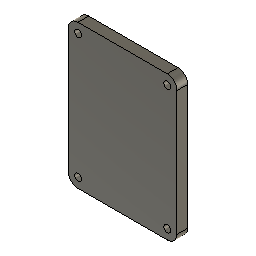
Total_Drone_Assembly_FinalVersion (Autodesk Fusion 360 archive; units mm, degrees)
design "Claw Mount"
Autodesk Fusion 360 part; units mm, degrees
sketch "Sketch1" plane through (0, 0, 0) normal (0, 1, 0) x (1, 0, 0)
  line L0 (20.785, 29) -> (-20.785, 29) construction
  line L1 (-20.785, 29) -> (-20.785, -29) construction
  line L2 (-20.785, -29) -> (20.785, -29) construction
  line L3 (20.785, -29) -> (20.785, 29) construction
  line L4 (20.785, 29) -> (-20.785, -29) construction
  line L5 (-20.785, 29) -> (20.785, -29) construction
  circle A0 centre (-20.785, -29) radius 1.6
  circle A1 centre (20.785, -29) radius 1.6
  circle A2 centre (-20.785, 29) radius 1.6
  circle A3 centre (20.785, 29) radius 1.6
  line L6 (-25.3048, 28.5198) -> (-25.3048, -28.5198)
  line L7 (-20.3048, -33.5198) -> (20.3048, -33.5198)
  line L8 (25.3048, -28.5198) -> (25.3048, 28.5198)
  line L9 (20.3048, 33.5198) -> (-20.3048, 33.5198)
  line L10 (-25.3048, -28.5198) -> (-25.3048, -33.5198)
  line L11 (-25.3048, -33.5198) -> (-20.3048, -33.5198)
  line L12 (0, 0) -> (4, 0) construction
  line L13 (0, 0) -> (0, -6) construction
  line L14 (25.3048, -28.5198) -> (25.3048, -33.5198)
  line L15 (25.3048, -33.5198) -> (20.3048, -33.5198)
  line L16 (-25.3048, 28.5198) -> (-25.3048, 33.5198)
  line L17 (-25.3048, 33.5198) -> (-20.3048, 33.5198)
  line L18 (25.3048, 33.5198) -> (20.3048, 33.5198)
  line L19 (25.3048, 28.5198) -> (25.3048, 33.5198)
  dimension "d2" = 58
  dimension "d3" = 3.2
  dimension "d8" = 41.57
  constraint horizontal L0
  constraint perpendicular L0 L1
  constraint parallel L0 L2
  constraint parallel L1 L3
  constraint coincident L4 L12.start
  constraint coincident L5 L12.start
  constraint coincident L12.start L13.start
  constraint coincident L1.end L2.start
  constraint coincident L2.end L3.start
  constraint coincident L0.end L1.start
  constraint coincident L0.start L3.end
  constraint equal A0 A1
  constraint equal A1 A2
  constraint equal A1 A3
  constraint perpendicular L7 L10
  constraint perpendicular L10 L11
  constraint horizontal L12
  constraint perpendicular L12 L13
  constraint symmetric L6.end L13 L8.start
  constraint symmetric L7.start L13 L7.end
  constraint symmetric L10.end L13 L14.end
  constraint symmetric L6.end L12 L6.start
  constraint symmetric L7.start L12 L9.end
  constraint symmetric L10.end L12 L16.end
  constraint symmetric L12 L8.start L8.end
  constraint symmetric L12 L14.end L18.start
  constraint symmetric L12 L7.end L9.start
  measures "d2" distance of L0 L2
  measures "d3" diameter of A0
  measures "d8" distance of L0.end L0.start
extrude "Extrude1" add sketch "Sketch1" against normal blind 5
fillet "Fillet1" radius 4.5 1 edges at (25.3048, -2.5, 33.5198)
fillet "Fillet1" radius 4.5 1 edges at (-25.3048, -2.5, 33.5198)
fillet "Fillet1" radius 4.5 1 edges at (-25.3048, -2.5, -33.5198)
fillet "Fillet1" radius 4.5 1 edges at (25.3048, -2.5, -33.5198)

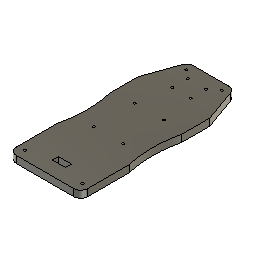
design "Upper Frame Plate"
Autodesk Fusion 360 part; units mm, degrees
sketch "Sketch2" plane through (0, 0, 0) normal (0, 0, 1) x (1, 0, 0)
  arc A0 (50.78, 25.1156) -> (50.78, -49.0914) centre (208.9874, -11.9879) ccw
  arc A1 (-50.78, -49.0914) -> (-50.78, 25.1156) centre (-208.9874, -11.9879) ccw
  circle A2 centre (-20.7745, -27.75) radius 1.6
  circle A3 centre (20.7855, -27.75) radius 1.6
  line L0 (50.78, 117.78) -> (-50.78, -117.78) construction
  line L1 (-50.78, 117.78) -> (50.78, -117.78) construction
  arc A4 (-50.78, -107.78) -> (-40.78, -117.78) centre (-40.78, -107.78) ccw
  line L2 (0, 0) -> (-7.4341, 0) construction
  line L3 (50.78, 65.1233) -> (50.78, 25.1156)
  circle A5 centre (40.78, -105.28) radius 1.6
  line L4 (-50.78, 65.1233) -> (-34.4616, 111.1233)
  line L5 (-50.78, 65.1233) -> (-50.78, 25.1156)
  circle A6 centre (-40.78, -105.28) radius 1.6
  circle A7 centre (25.0371, 107.78) radius 1.6
  line L6 (50.78, 65.1233) -> (34.4616, 111.1233)
  line L7 (-50.78, -65.1233) -> (50.78, -65.1233) construction
  line L8 (-50.78, -49.0914) -> (-50.78, -107.78)
  line L9 (0, 0) -> (0, 7) construction
  line L10 (-40.78, -117.78) -> (40.78, -117.78)
  line L11 (-51.3517, 117.78) -> (-25.0371, 117.78)
  line L12 (50.78, -107.78) -> (50.78, -49.0914)
  line L13 (-50.78, 65.1233) -> (50.78, 65.1233) construction
  circle A8 centre (-25.0371, 107.78) radius 1.6
  arc A9 (40.78, -117.78) -> (50.78, -107.78) centre (40.78, -107.78) ccw
  arc A10 (34.4616, 111.1233) -> (25.0371, 117.78) centre (25.0371, 107.78) ccw
  circle A11 centre (20.7855, 30.25) radius 1.6
  line L14 (-40.78, -107.78) -> (-45.5769, -105.7118)
  circle A12 centre (-20.7745, 30.25) radius 1.6
  arc A13 (-25.0371, 117.78) -> (-34.4616, 111.1233) centre (-25.0371, 107.78) ccw
  line L15 (-51.3517, 117.78) -> (25.0371, 117.78)
  line L16 (0, 0) -> (0, -8) construction
  line L17 (-9.25, -89.28) -> (9.25, -89.28)
  line L18 (9.25, -89.28) -> (9.25, -97.78)
  line L19 (9.25, -97.78) -> (-9.25, -97.78)
  line L20 (-9.25, -97.78) -> (-9.25, -89.28)
  line L21 (-9.25, -89.28) -> (9.25, -97.78) construction
  line L22 (9.25, -89.28) -> (-9.25, -97.78) construction
  circle A14 centre (12.78, 76.16) radius 1.6
  circle A15 centre (-13.22, 76.16) radius 1.6
  circle A16 centre (12.78, 97.78) radius 1.6
  circle A17 centre (-13.22, 97.78) radius 1.6
  point P0 (-50.78, -49.0914)
  point P1 (25.2318, 134.4238)
  point P2 (-20.0717, 32.7459)
  point P3 (0, -15.28)
  point P4 (0, 15)
  point P5 (0, 55)
  point P6 (0, -55)
  point P7 (-20.0606, -58.0786)
  point P8 (20.4874, -58.0786)
  point P9 (0, -93.53)
  dimension "d145" = 41.56
  dimension "d146" = 101.56
  dimension "d147" = 235.56
  dimension "d148" = 60.5
  dimension "d149" = 30.0055
  dimension "d150" = 145.53
  dimension "d151" = 10
  dimension "d152" = 10
  dimension "d156" = 15.28
  dimension "d159" = 160.468
  dimension "d160" = 10
  dimension "d161" = 46
  dimension "d162" = 110
  dimension "d163" = 162.5
  dimension "d164" = 208.9874
  dimension "d165" = 105.7921
  dimension "d166" = 3.2
  dimension "d167" = 3.2
  dimension "d168" = 3.2
  dimension "d169" = 3.2
  dimension "d170" = 3.2
  dimension "d171" = 3.2
  dimension "d172" = 3.2
  dimension "d173" = 3.2
  dimension "d176" = 101.56
  dimension "d189" = 18.5
  dimension "d190" = 8.5
  dimension "d191" = 20
  dimension "d195" = 90.03
  dimension "d196" = 3.2
  dimension "d197" = 3.2
  dimension "d198" = 26
  dimension "d200" = 38
  dimension "d201" = 3.2
  dimension "d203" = 3.2
  dimension "d204" = 21.62
  dimension "d207" = 20
  dimension "d208" = 26
  dimension "d209" = 21.62
  constraint coincident L2.start L9.start
  constraint horizontal L11
  constraint perpendicular L5 L11
  constraint parallel L10 L11
  constraint parallel L5 L12
  constraint coincident L2.start L0
  constraint coincident L2.start L1
  constraint coincident L0.end L5
  constraint coincident L0.end L10
  constraint tangent A4 L5
  constraint tangent A4 L10
  constraint coincident L1.end L12
  constraint coincident L1.end L10
  constraint tangent L12 A9
  constraint tangent L10 A9
  constraint coincident L1.start L11
  constraint coincident L1.start L5
  constraint coincident L0.start L11
  constraint coincident L0.start L12
  constraint coincident A4.centre L14.start
  constraint coincident L14.end L0
  constraint perpendicular L0 L14
  constraint horizontal L2
  constraint perpendicular L2 L9
  constraint symmetric L4.start L3.start L9
  constraint tangent L11 A13
  constraint tangent L4 A13
  constraint symmetric L4.start L7.start L2
  constraint symmetric L7.end L3.start L2
  constraint coincident P0 L5
  constraint coincident P0 A1.start
  constraint coincident A1.end L5.end
  constraint symmetric A0.start A1.end L9
  constraint symmetric A0.end P0 L9
  constraint symmetric A0 A1 L9
  constraint collinear L5 L8
  constraint symmetric A10.end L11.end L9
  constraint symmetric L6.end L4.end L9
  constraint symmetric L9 A10 A13
  constraint parallel L11 L15
  constraint concentric A8 A13
  constraint concentric A7 A10
  constraint horizontal A3.centre A2.centre
  constraint parallel L9 L16
  constraint horizontal L17
  constraint perpendicular L17 L18
  constraint parallel L17 L19
  constraint parallel L18 L20
  constraint coincident L21 P9
  constraint coincident L22 P9
  constraint vertical L2.start P9
  constraint horizontal A14.centre A15.centre
  constraint vertical A14.centre A16.centre
  measures "d145" distance of A3.centre A2.centre
  measures "d146" distance of L0.start L1.start
  measures "d147" distance of L0.end L1.start
  measures "d148" distance of P2 A2.centre
  measures "d149" distance of A2.centre L5
  measures "d150" distance of A2.centre L11
  measures "d151" radius of A4
  measures "d152" radius of A9
  measures "d156" distance of P3 L2.start
  measures "d159" angle of L4 L5
  measures "d160" radius of A13
  measures "d161" vertical distance of L4.start L4.end
  measures "d162" distance of P5 P6
  measures "d163" radius of A1
  measures "d164" horizontal distance of A1.centre L2.start
  measures "d165" distance of A1.centre L10
  measures "d166" diameter of A8
  measures "d167" diameter of A7
  measures "d168" diameter of A6
  measures "d169" diameter of A5
  measures "d170" diameter of A2
  measures "d171" diameter of A3
  measures "d172" diameter of A11
  measures "d173" diameter of A12
  measures "d176" distance of L8 L12
  measures "d189" distance of L17.start L17.end
  measures "d190" distance of L17.end L18.end
  measures "d191" distance of L10 L19
  measures "d195" distance of A3.centre L10
  measures "d196" diameter of A14
  measures "d197" diameter of A15
  measures "d198" horizontal distance of A14.centre A15.centre
  measures "d200" distance of L3 A14.centre
  measures "d201" diameter of A16
  measures "d203" diameter of A17
  measures "d204" vertical distance of A15.centre A17.centre
  measures "d207" distance of L11 A17.centre
  measures "d208" distance of A16.centre A17.centre
  measures "d209" distance of A14.centre A16.centre
extrude "Extrude10" add sketch "Sketch2" along normal blind 10 contours A0 A1 A4 L3 L4 L5 L6 L8 L10 L12 A9 A10 A13 L15 | A14 | A15 | A16 | A17
extrude "Extrude11" cut sketch "Sketch2" along normal blind 25 contours A14 | A15 | A16 | A17

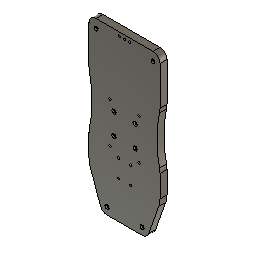
design "Center Chassis Plate"
Autodesk Fusion 360 part; units mm, degrees
sketch "Sketch1" plane through (0, 0, 0) normal (0, 1, 0) x (1, 0, 0)
  line L0 (24.9942, 117.78) -> (-25.0371, 117.78)
  line L1 (-40.78, -117.78) -> (40.78, -117.78)
  line L2 (50.78, 117.78) -> (-50.78, -117.78) construction
  line L3 (-50.78, 117.78) -> (50.78, -117.78) construction
  arc A0 (-50.78, -107.78) -> (-40.78, -117.78) centre (-40.78, -107.78) ccw
  arc A1 (40.78, -117.78) -> (50.78, -107.78) centre (40.78, -107.78) ccw
  line L4 (-40.78, -107.78) -> (-45.5769, -105.7118)
  circle A2 centre (-15.28, -15.28) radius 1.6
  circle A3 centre (15.28, -15.28) radius 1.6
  line L5 (0, 0) -> (-7.4341, 0) construction
  circle A4 centre (-15.28, 15.28) radius 1.6
  circle A5 centre (15.28, 15.28) radius 1.6
  line L6 (-50.78, 65.1233) -> (-34.4616, 111.1233)
  line L7 (0, 0) -> (0, -8) construction
  arc A6 (-25.0371, 117.78) -> (-34.4616, 111.1233) centre (-25.0371, 107.78) ccw
  line L8 (-50.78, 65.1233) -> (50.78, 65.1233) construction
  line L9 (-50.78, -65.1233) -> (50.78, -65.1233) construction
  arc A7 (-50.78, -49.0914) -> (-50.78, 25.1156) centre (-208.9874, -11.9879) ccw
  arc A8 (50.78, 25.1156) -> (50.78, -49.0914) centre (208.9874, -11.9879) ccw
  line L10 (-50.78, 65.1233) -> (-50.78, 25.1156)
  line L11 (-50.78, -49.0914) -> (-50.78, -107.78)
  line L12 (50.78, -107.78) -> (50.78, -49.0914)
  line L13 (50.78, 65.1233) -> (50.78, 25.1156)
  line L14 (50.78, 65.1233) -> (34.4616, 111.1233)
  arc A9 (34.4616, 111.1233) -> (25.0371, 117.78) centre (25.0371, 107.78) ccw
  line L15 (24.9942, 117.78) -> (25.0371, 117.78)
  circle A10 centre (-25.0371, 107.78) radius 1.6
  circle A11 centre (25.0371, 107.78) radius 1.6
  circle A12 centre (-40.78, -105.28) radius 2.6
  circle A13 centre (40.78, -105.28) radius 2.6
  circle A14 centre (-20.7745, -27.75) radius 1.6
  circle A15 centre (20.7855, -27.75) radius 1.6
  circle A16 centre (20.7855, 30.25) radius 1.6
  circle A17 centre (-20.7745, 30.25) radius 1.6
  circle A18 centre (-7.37, -112.38) radius 1.6
  circle A19 centre (0, -112.38) radius 1.6
  circle A20 centre (7.37, -112.38) radius 1.6
  point P0 (25.2318, 134.4238)
  point P1 (-20.0606, -58.0786)
  point P2 (20.4874, -58.0786)
  point P3 (-20.1592, 32.7469)
  point P4 (0, -15.28)
  point P5 (0, 15)
  point P6 (0, 55)
  point P7 (0, -55)
  point P8 (-50.78, -49.0914)
  dimension "d118" = 41.56
  dimension "d129" = 101.56
  dimension "d130" = 235.56
  dimension "d132" = 60.5
  dimension "d138" = 30.0055
  dimension "d139" = 145.53
  dimension "d140" = 10
  dimension "d141" = 10
  dimension "d144" = 3.2
  dimension "d145" = 3.2
  dimension "d146" = 30.56
  dimension "d147" = 15.28
  dimension "d150" = 30.56
  dimension "d151" = 35.5
  dimension "d152" = 160.468
  dimension "d154" = 10
  dimension "d155" = 46
  dimension "d164" = 110
  dimension "d165" = 162.5
  dimension "d166" = 208.9874
  dimension "d167" = 105.7921
  dimension "d169" = 3.2
  dimension "d170" = 3.2
  dimension "d222" = 5.2
  dimension "d223" = 5.2
  dimension "d224" = 3.2
  dimension "d225" = 3.2
  dimension "d226" = 3.2
  dimension "d227" = 3.2
  dimension "d236" = 3.2
  dimension "d237" = 5.4
  dimension "d238" = 101.56
  dimension "d239" = 43.41
  dimension "d240" = 43.41
  dimension "d241" = 7.37
  constraint coincident L5.start L7.start
  constraint horizontal L0
  constraint perpendicular L0 L10
  constraint parallel L0 L1
  constraint parallel L10 L12
  constraint coincident L2 L5.start
  constraint coincident L3 L5.start
  constraint coincident L2.end L10
  constraint coincident L2.end L1
  constraint tangent A0 L10
  constraint tangent L1 A0
  constraint coincident L3.end L12
  constraint coincident L3.end L1
  constraint tangent A1 L12
  constraint tangent L1 A1
  constraint coincident L3.start L0
  constraint coincident L3.start L10
  constraint coincident L2.start L0
  constraint coincident L2.start L12
  constraint coincident A0.centre L4.start
  constraint coincident L2 L4.end
  constraint perpendicular L2 L4
  constraint horizontal A2.centre A3.centre
  constraint horizontal L5
  constraint symmetric A2 L5 A4
  constraint symmetric A3 L5 A5
  constraint perpendicular L5 L7
  constraint symmetric L6.start L7 L8.end
  constraint tangent L0 A6
  constraint tangent L6 A6
  constraint symmetric L5 L6.start L9.start
  constraint symmetric L5 L8.end L9.end
  constraint coincident P8 L10
  constraint coincident P8 A7.start
  constraint coincident A7.end L10.end
  constraint symmetric L7 A7.end A8.start
  constraint symmetric L7 P8 A8.end
  constraint symmetric L7 A7 A8
  constraint collinear L10 L11
  constraint symmetric L7 L0.end A9.end
  constraint symmetric L7 L6.end L14.end
  constraint symmetric L7 A6 A9
  constraint parallel L0 L15
  constraint concentric A6 A10
  constraint concentric A9 A11
  constraint horizontal A14.centre A15.centre
  constraint equal A18 A19
  constraint equal A18 A20
  constraint horizontal A18.centre A19.centre
  constraint horizontal A19.centre A20.centre
  measures "d118" distance of A14.centre A15.centre
  measures "d129" distance of L2.start L3.start
  measures "d130" distance of L3.start L2.end
  measures "d132" distance of P3 A14.centre
  measures "d138" distance of L10 A14.centre
  measures "d139" distance of L0 A14.centre
  measures "d140" radius of A0
  measures "d141" radius of A1
  measures "d144" diameter of A2
  measures "d145" diameter of A3
  measures "d146" horizontal distance of A2.centre A3.centre
  measures "d147" distance of L5.start P4
  measures "d150" distance of A2.centre A4.centre
  measures "d151" distance of A2.centre L10
  measures "d152" angle of L6 L10
  measures "d154" radius of A6
  measures "d155" vertical distance of L6.start L6.end
  measures "d164" distance of P6 P7
  measures "d165" radius of A7
  measures "d166" horizontal distance of L5.start A7.centre
  measures "d167" distance of L1 A7.centre
  measures "d169" diameter of A10
  measures "d170" diameter of A11
  measures "d222" diameter of A12
  measures "d223" diameter of A13
  measures "d224" diameter of A14
  measures "d225" diameter of A15
  measures "d226" diameter of A16
  measures "d227" diameter of A17
  measures "d236" diameter of A18
  measures "d237" distance of L1 A18.centre
  measures "d238" distance of L11 L12
  measures "d239" distance of L11 A18.centre
  measures "d240" distance of L12 A20.centre
  measures "d241" distance of A18.centre A19.centre
extrude "Extrude7" add sketch "Sketch1" along normal blind 10
fillet "Fillet3" radius 30 1 edges at (-50.78, 5, -25.1156)
fillet "Fillet3" radius 30 1 edges at (50.78, 5, -25.1156)
fillet "Fillet4" radius 30 1 edges at (-50.78, 5, -65.1233)
fillet "Fillet4" radius 30 1 edges at (50.78, 5, -65.1233)
fillet "Fillet5" radius 30 1 edges at (50.78, 5, 49.0914)
fillet "Fillet5" radius 30 1 edges at (-50.78, 5, 49.0914)
ref_plane "WorkPlane1" through (0, 0, 0) normal (0, -1, 0) x (-1, 0, 0)
sketch "Sketch5" plane through (0, 0, 0) normal (0, -1, 0) x (-1, 0, 0)
  circle A0 centre (102.6984, -70.0244) radius 17.5
  line L0 (20.6309, -40.2485) -> (92.7317, -84.409)
  line L1 (21.8829, -25.3315) -> (108.112, -53.3828)
  circle A1 centre (20.78, -32.75) radius 7.5
  line L2 (0, 0) -> (0, -8.4587)
  circle A2 centre (-20.78, -32.75) radius 7.5
  line L3 (0, 0) -> (-10, 0)
  circle A3 centre (20.78, 32.75) radius 7.5
  circle A4 centre (-20.78, 32.75) radius 7.5
  circle A5 centre (102.6984, -70.0244) radius 16.95
  circle A6 centre (102.6984, -70.0244) radius 2.625
  circle A7 centre (102.6984, -70.0244) radius 9.5 construction
  circle A8 centre (102.6984, -79.5244) radius 1.625
  circle A9 centre (112.1984, -70.0244) radius 1.625
  circle A10 centre (102.6983, -60.5244) radius 1.625
  circle A11 centre (93.1984, -70.0244) radius 1.625
  line L4 (40.78, -117.78) -> (-40.78, -117.78)
  line L5 (50.78, -52.4134) -> (50.78, -107.78)
  line L6 (16.8434, 12.5301) -> (18.4311, 15.2801)
  line L7 (18.4311, 15.2801) -> (16.8434, 18.0301)
  line L8 (16.8434, 18.0301) -> (13.668, 18.0301)
  line L9 (13.668, 18.0301) -> (12.0803, 15.2801)
  line L10 (12.0803, 15.2801) -> (13.668, 12.5301)
  line L11 (13.668, 12.5301) -> (16.8434, 12.5301)
  line L12 (0, 0) -> (0, -8)
  line L13 (-12.0803, 15.2801) -> (-13.668, 12.5301)
  line L14 (-13.668, 18.0301) -> (-12.0803, 15.2801)
  line L15 (-16.8434, 18.0301) -> (-13.668, 18.0301)
  line L16 (-18.4311, 15.2801) -> (-16.8434, 18.0301)
  line L17 (-16.8434, 12.5301) -> (-18.4311, 15.2801)
  line L18 (-13.668, 12.5301) -> (-16.8434, 12.5301)
  line L19 (-13.668, -12.5301) -> (-16.8434, -12.5301)
  line L20 (-12.0803, -15.2801) -> (-13.668, -12.5301)
  line L21 (-13.668, -18.0301) -> (-12.0803, -15.2801)
  line L22 (-16.8434, -18.0301) -> (-13.668, -18.0301)
  line L23 (-18.4311, -15.2801) -> (-16.8434, -18.0301)
  line L24 (-16.8434, -12.5301) -> (-18.4311, -15.2801)
  line L25 (13.668, -18.0301) -> (12.0803, -15.2801)
  line L26 (16.8434, -18.0301) -> (13.668, -18.0301)
  line L27 (18.4311, -15.2801) -> (16.8434, -18.0301)
  line L28 (16.8434, -12.5301) -> (18.4311, -15.2801)
  line L29 (13.668, -12.5301) -> (16.8434, -12.5301)
  line L30 (12.0803, -15.2801) -> (13.668, -12.5301)
  line L31 (23.5017, 105.0004) -> (26.6766, 105.0606)
  line L32 (26.6766, 105.0606) -> (28.2119, 107.8401)
  line L33 (28.2119, 107.8401) -> (26.5724, 110.5596)
  line L34 (26.5724, 110.5596) -> (23.3976, 110.4994)
  line L35 (23.3976, 110.4994) -> (21.8622, 107.7199)
  line L36 (21.8622, 107.7199) -> (23.5017, 105.0004)
  line L37 (38.0249, -106.8588) -> (40.7697, -108.4554)
  line L38 (40.7697, -108.4554) -> (43.5248, -106.8766)
  line L39 (43.5248, -106.8766) -> (43.5351, -103.7012)
  line L40 (43.5351, -103.7012) -> (40.7903, -102.1046)
  line L41 (40.7903, -102.1046) -> (38.0352, -103.6834)
  line L42 (38.0352, -103.6834) -> (38.0249, -106.8588)
  line L43 (-43.5351, -103.7012) -> (-40.7903, -102.1046)
  line L44 (-40.7697, -108.4554) -> (-43.5248, -106.8766)
  line L45 (-40.7903, -102.1046) -> (-38.0352, -103.6834)
  line L46 (-43.5248, -106.8766) -> (-43.5351, -103.7012)
  line L47 (-38.0249, -106.8588) -> (-40.7697, -108.4554)
  line L48 (-38.0352, -103.6834) -> (-38.0249, -106.8588)
  line L49 (-21.8622, 107.7199) -> (-23.5017, 105.0004)
  line L50 (-23.5017, 105.0004) -> (-26.6766, 105.0606)
  line L51 (-23.3976, 110.4994) -> (-21.8622, 107.7199)
  line L52 (-26.6766, 105.0606) -> (-28.2119, 107.8401)
  line L53 (-26.5724, 110.5596) -> (-23.3976, 110.4994)
  line L54 (-28.2119, 107.8401) -> (-26.5724, 110.5596)
  point P0 (15.2557, 15.2801)
  point P1 (15.2557, 15.2801)
  point P2 (15.28, 15.28)
  point P3 (25.0371, 107.78)
  point P4 (25.0371, 107.78)
  point P5 (25.0371, 107.78)
  point P6 (40.78, -105.28)
  point P7 (40.78, -105.28)
  point P8 (-40.78, -105.28)
  point P9 (-40.78, -105.28)
  point P10 (-25.0371, 107.78)
  point P11 (-25.0371, 107.78)
  point P12 (-25.0371, 107.78)
  dimension "d188" = 35
  dimension "d189" = 15
  dimension "d190" = 33.9
  dimension "d191" = 5.25
  dimension "d192" = 19
  dimension "d193" = 3.25
  dimension "d195" = 360
  dimension "d196" = 19
  dimension "d197" = 90
  dimension "d198" = 85.03
  dimension "d199" = 30
  dimension "d212" = 5.5
  dimension "d214" = 12.0803
  dimension "d215" = 12.5301
  dimension "d218" = 5.5
  dimension "d219" = 5.5
  constraint coincident A0 L0.end
  constraint coincident A0 L1.end
  constraint tangent A0 L1
  constraint coincident L2.start L3.start
  constraint vertical L2
  constraint symmetric A1 L2 A2
  constraint horizontal L3
  constraint symmetric A1 L3 A3
  constraint symmetric A2 L3 A4
  constraint coincident L0.start A1
  constraint coincident L1.start A1
  constraint concentric A0 A5
  constraint concentric A5 A6
  constraint concentric A0 A7
  constraint coincident A7 A8.centre
  constraint coincident P1 P0
  constraint horizontal L11
  constraint symmetric L6.start L12 L17.start
  constraint symmetric L6.end L12 L16.start
  constraint symmetric L7.end L12 L15.start
  constraint symmetric L8.end L12 L14.start
  constraint symmetric L9.end L12 L13.start
  constraint symmetric L10.end L12 L13.end
  constraint symmetric L3 L6.start L28.start
  constraint symmetric L3 L6.end L27.start
  constraint symmetric L3 L7.end L26.start
  constraint symmetric L3 L8.end L25.start
  constraint symmetric L3 L9.end L25.end
  constraint symmetric L3 L10.end L29.start
  constraint symmetric L3 L13.start L20.start
  constraint symmetric L3 L13.end L19.start
  constraint symmetric L3 L14.start L21.start
  constraint symmetric L3 L15.start L22.start
  constraint symmetric L3 L16.start L23.start
  constraint symmetric L3 L17.start L19.end
  constraint coincident P5 P4
  constraint coincident P7 P6
  constraint symmetric L2 P5 P12
  constraint symmetric L2 L31.start L49.end
  constraint symmetric L2 L31.end L50.end
  constraint symmetric L2 L32.end L52.end
  constraint symmetric L2 L33.end L53.start
  constraint symmetric L2 L34.end L51.start
  constraint symmetric L2 L35.end L49.start
  constraint symmetric L2 P7 P9
  constraint symmetric L2 L37.start L47.start
  constraint symmetric L2 L37.end L44.start
  constraint symmetric L2 L38.end L44.end
  constraint symmetric L2 L39.end L43.start
  constraint symmetric L2 L40.end L43.end
  constraint symmetric L2 L41.end L45.end
  measures "d188" diameter of A0
  measures "d189" diameter of A1
  measures "d190" diameter of A5
  measures "d191" diameter of A6
  measures "d192" diameter of A7
  measures "d193" diameter of A8
  measures "d196" horizontal distance of A9.centre A11.centre
  measures "d197" distance of A1.centre A0.centre
  measures "d198" distance of A1.centre L4
  measures "d199" distance of A1.centre L5
  measures "d212" distance of L8 L11
  measures "d214" horizontal distance of L9.end L2.start
  measures "d215" distance of L11 L2.start
  measures "d218" distance of L31 L34
  measures "d219" distance of L39 L42
extrude "Extrude9" cut sketch "Sketch5" against normal blind 2.5 contours L6 L7 L8 L9 L10 L11 | L13 L14 L15 L16 L17 L18 | L19 L20 L21 L22 L23 L24 | L25 L26 L27 L28 L29 L30
extrude "Extrude10" cut sketch "Sketch5" against normal blind 2.5 contours L6 L7 L8 L9 L10 L11 | L13 L14 L15 L16 L17 L18 | L19 L20 L21 L22 L23 L24 | L25 L26 L27 L28 L29 L30 | L31 L32 L33 L34 L35 L36 | L37 L38 L39 L40 L41 L42 | L43 L44 L45 L46 L47 L48 | L49 L50 L51 L52 L53 L54
sketch "Sketch6" plane through (0, 10, 0) normal (0, 1, 0) x (-1, 0, 0)
  line L0 (50.78, 52.4134) -> (50.78, 107.78)
  arc A0 (50.78, 107.78) -> (40.78, 117.78) centre (40.78, 107.78) ccw
  line L1 (40.78, 117.78) -> (-40.78, 117.78)
  arc A1 (-40.78, 117.78) -> (-50.78, 107.78) centre (-40.78, 107.78) ccw
  line L2 (-50.78, 107.78) -> (-50.78, 52.4134)
  arc A2 (-50.78, -59.9598) -> (-49.0536, -69.9898) centre (-20.78, -59.9598) ccw
  line L3 (-49.0536, -69.9898) -> (-34.4616, -111.1233)
  arc A3 (-34.4616, -111.1233) -> (-25.0371, -117.78) centre (-25.0371, -107.78) ccw
  line L4 (-24.9942, -117.78) -> (25.0371, -117.78)
  arc A4 (25.0371, -117.78) -> (34.4616, -111.1233) centre (25.0371, -107.78) ccw
  line L5 (34.4616, -111.1233) -> (49.0536, -69.9898)
  arc A5 (49.0536, -69.9898) -> (50.78, -59.9598) centre (20.78, -59.9598) ccw
  circle A6 centre (-40.78, 107.78) radius 2.6
  circle A7 centre (25.0371, -107.78) radius 1.6
  circle A8 centre (-25.0371, -107.78) radius 1.6
  circle A9 centre (40.78, 107.78) radius 2.6
  circle A10 centre (0, 112.38) radius 1.6
  circle A11 centre (7.37, 112.38) radius 1.6
  circle A12 centre (-7.37, 112.38) radius 1.6
  line L6 (-25.0371, -117.78) -> (-24.9942, -117.78)
  circle A13 centre (8.78, -39.25) radius 1.6
  circle A14 centre (20.7745, -30.25) radius 1.6
  line L7 (50.78, -59.9598) -> (50.78, -28.4376)
  circle A15 centre (-8.72, -39.25) radius 1.6
  circle A16 centre (8.78, -64.25) radius 1.6
  circle A17 centre (-8.72, -64.25) radius 1.6
  point P0 (-40.78, 105.28)
  point P1 (40.78, 105.28)
  point P2 (40.78, 105.28)
  point P3 (-40.78, 105.28)
  point P4 (40.78, 105.28)
  point P5 (-40.78, 105.28)
  point P6 (-40.78, 105.28)
  point P7 (40.78, 105.28)
  point P8 (40.78, 105.28)
  point P9 (-40.78, 105.28)
  point P10 (40.78, 105.28)
  point P11 (-40.78, 105.28)
  point P12 (40.78, 105.28)
  point P13 (-40.78, 105.28)
  dimension "d247" = 3.2
  dimension "d248" = 9
  dimension "d249" = 42
  dimension "d250" = 17.5
  dimension "d251" = 25
  dimension "d252" = 17.5
  constraint equal A13 A15
  constraint horizontal A13.centre A15.centre
  constraint equal A13 A16
  constraint vertical A13.centre A16.centre
  constraint equal A16 A17
  constraint horizontal A16.centre A17.centre
  measures "d247" diameter of A13
  measures "d248" vertical distance of A13.centre A14.centre
  measures "d249" distance of A13.centre L7
  measures "d250" distance of A13.centre A15.centre
  measures "d251" distance of A13.centre A16.centre
  measures "d252" distance of A16.centre A17.centre
extrude "Extrude12" cut sketch "Sketch6" against normal blind 65 contours A13 | A15 | A16 | A17

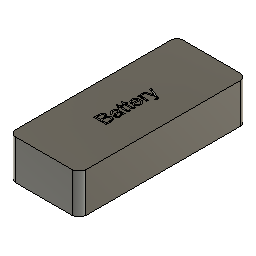
design "OVONIC 6S LiPo Battery 5200mAh 22.2V 130C"
part number: 2026-10-01-21-12-21-860
Autodesk Fusion 360 part; units mm, degrees
sketch "Sketch1" plane through (0, 0, 0) normal (1, 0, 0) x (0, 1, 0)
  line L0 (0, 0) -> (134.112, 0)
  line L1 (134.112, 0) -> (134.112, 31.75)
  line L2 (134.112, 31.75) -> (0, 31.75)
  line L3 (0, 31.75) -> (0, 0)
  dimension "d1" = 134.112
  dimension "d2" = 31.75
  constraint horizontal L0
  constraint vertical L1
  constraint horizontal L2
  constraint vertical L3
  constraint coincident L0.start L3.end
  measures "d1" distance of L0.start L0.end
  measures "d2" distance of L0.start L2.end
extrude "Extrude1" add sketch "Sketch1" along normal blind 55.88
fillet "Fillet1" radius 5 tangency weight 0.1591 1 edges at (55.88, 0, 15.875)
fillet "Fillet2" radius 5 1 edges at (0, 0, 15.875)
sketch "Sketch2" plane through (0, 0, 31.75) normal (0, 0, 1) x (-1, 0, 0)
  arc A0 (0, -5) -> (-5, 0) centre (-5, -5) ccw
  line L0 (-5, 0) -> (-50.88, 0)
  spline S0 degree 3 poles (-55.88, -5) (-55.88, -4.9799) (-55.8752, -4.9579) (-55.8516, -4.8768) (-55.813, -4.8022) (-55.6173, -4.4631) (-55.2829, -4.0319) (-54.0532, -2.6354) (-53.0098, -1.5988) (-51.9563, -0.7005) (-51.5688, -0.3759) (-51.1806, -0.1255) (-51.0922, -0.0723) (-50.989, -0.0266) (-50.9617, -0.0159) (-50.918, -0.004) (-50.8982, 0) (-50.88, 0) knots 0 0 0 0 0.006017 0.006017 0.025433 0.025433 0.109859 0.109859 0.253011 0.253011 0.282328 0.282328 0.288979 0.288979 0.291079 0.291079 0.292488 0.292488 0.292488 0.292488
  line L1 (-55.88, -5) -> (-55.88, -134.112)
  line L2 (-55.88, -134.112) -> (0, -134.112)
  line L3 (0, -134.112) -> (0, -5)
  line L4 (-38.8009, -44.8482) -> (-38.8009, -132.5244) construction
  line L5 (-38.8009, -132.5244) -> (-22.6971, -132.5244) construction
  line L6 (-22.6971, -132.5244) -> (-22.6971, -44.8482) construction
  line L7 (-22.6971, -44.8482) -> (-38.8009, -44.8482) construction
  dimension "d9" = 10
  text T0 "Battery" font "Arial" height 10 align left top in box 87.6762 x 16.1038 at (-38.8009, -44.8482) x (0, -1) y (1, 0) spacing 1 kerned
extrude "Extrude2" cut sketch "Sketch2" against normal blind 5 text T0
fillet "Fillet3" radius 5 1 edges at (55.88, 134.112, 15.875)
fillet "Fillet3" radius 5 1 edges at (0, 134.112, 15.875)
equation "d10 = 'Battery'"

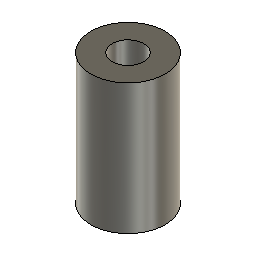
design "Frame Spacer"
Autodesk Fusion 360 part; units mm, degrees
sketch "Sketch1" plane through (0, 0, 0) normal (0, 0, 1) x (1, 0, 0)
  circle A0 centre (0, 0) radius 5
  circle A1 centre (0, 0) radius 2.125
  dimension "d1" = 10
  dimension "d2" = 4.25
  constraint coincident A0.centre A1.centre
  measures "d1" diameter of A0
  measures "d2" diameter of A1
extrude "Extrude1" add sketch "Sketch1" along normal blind 17.6
equation "d3 = ( 20 mm - 2.4 mm )"

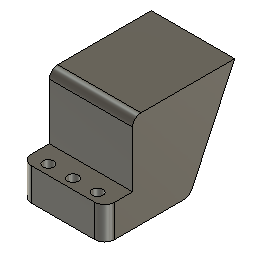
design "GPS Mount"
part number: 2026-10-01-21-19-52-658
Autodesk Fusion 360 part; units mm, degrees
sketch "Sketch1" plane through (0, 0, 0) normal (0, 1, 0) x (1, 0, 0)
  line L0 (-12.5, -14.5) -> (12.5, -14.5)
  line L1 (12.5, -14.5) -> (12.5, 14.5)
  line L2 (12.5, 14.5) -> (-12.5, 14.5)
  line L3 (-12.5, 14.5) -> (-12.5, -14.5)
  line L4 (-12.5, -14.5) -> (12.5, 14.5) construction
  line L5 (12.5, -14.5) -> (-12.5, 14.5) construction
  dimension "d6" = 25
  dimension "d7" = 29
  constraint horizontal L0
  constraint perpendicular L0 L1
  constraint parallel L0 L2
  constraint parallel L1 L3
  constraint coincident L4 origin
  constraint coincident L5 origin
  measures "d6" distance of L1.end L2.end
  measures "d7" distance of L0.end L1.end
extrude "Extrude2" add sketch "Sketch1" along normal blind 29
draft "Draft1" angle -25 neutral plane through (-12.5, 0, 14.5) pull (0, 0, 1) 1 faces at (-4.1667, 29, 4.8333)
sketch "Sketch2" plane through (0, 18.2666, -8.5179) normal (0, 0.906308, -0.422618) x (-1, 0, 0)
  line L0 (12.5, -6.6006) -> (12.5, 25.3974)
  line L1 (12.5, 25.3974) -> (-12.5, 25.3974)
  line L2 (-12.5, 25.3974) -> (-12.5, -6.6006)
  line L3 (-12.5, -6.6006) -> (12.5, -6.6006)
  line L4 (0, -6.6006) -> (0, 25.3974) construction
  line L5 (-11, 20.3984) -> (11, 20.3984)
  line L6 (11, 20.3984) -> (11, -1.6016)
  line L7 (11, -1.6016) -> (-11, -1.6016)
  line L8 (-11, -1.6016) -> (-11, 20.3984)
  line L9 (-11, 20.3984) -> (11, -1.6016) construction
  line L10 (11, 20.3984) -> (-11, -1.6016) construction
  point P0 (0, 9.3984)
  point P1 (0, 9.3984)
  dimension "d12" = 22
  dimension "d13" = 22
  constraint midpoint L3 L4.start
  constraint midpoint L1 L4.end
  constraint midpoint L4 P1
  constraint horizontal L5
  constraint perpendicular L5 L6
  constraint parallel L5 L7
  constraint parallel L6 L8
  constraint coincident L9 P1
  constraint coincident L10 P1
  constraint coincident P1 P0
  measures "d12" distance of L5.start L5.end
  measures "d13" distance of L5 L7
extrude "Extrude3" cut sketch "Sketch2" against normal blind 9.2 contours L5 L6 L7 L8
fillet "Fillet2" radius 2.5 1 edges at (0, 0, 14.5)
sketch "Sketch3" plane through (0, 0, 0) normal (0, -1, 0) x (1, 0, 0)
  line L0 (12.5, 12) -> (-12.5, 12)
  line L1 (-12.5, 12) -> (-12.5, -14.5)
  line L2 (-12.5, -14.5) -> (12.5, -14.5)
  line L3 (12.5, -14.5) -> (12.5, 12)
  line L4 (12.5, -14.5) -> (-12.5, -14.5)
  line L5 (-12.5, -14.5) -> (-12.5, -4.7838)
  line L6 (-12.5, -4.7838) -> (12.5, -4.7838)
  line L7 (12.5, -4.7838) -> (12.5, -14.5)
  constraint horizontal L4
  constraint vertical L5
  constraint horizontal L6
  constraint vertical L7
  constraint coincident L1 L5.end
  constraint coincident L2.end L3.start
extrude "Extrude4" add sketch "Sketch3" along normal blind 10 contours L1 L2 L3 L4 L5 L6 L7
sketch "Sketch4" plane through (0, 0, -14.5) normal (0, 0, -1) x (1, 0, 0)
  line L0 (-12.5, 10) -> (-12.5, -15.4771)
  line L1 (-12.5, -15.4771) -> (12.5, -15.4771)
  line L2 (12.5, -15.4771) -> (12.5, 10)
  circle A0 centre (-7.37, 7) radius 1.6
  circle A1 centre (7.37, 7) radius 1.6
  circle A2 centre (0, 7) radius 1.6
  dimension "d22" = 3.2
  dimension "d24" = 5.13
  dimension "d26" = 7
  dimension "d27" = 7.37
  dimension "d29" = 5.13
  dimension "d30" = 14.74
  constraint equal A0 A1
  constraint horizontal A0.centre A1.centre
  constraint equal A0 A2
  constraint horizontal A0.centre A2.centre
  measures "d22" diameter of A0
  measures "d24" distance of L0 A0.centre
  measures "d26" vertical distance of origin A0.centre
  measures "d27" distance of A0.centre A2.centre
  measures "d29" distance of L2 A1.centre
  measures "d30" distance of A0.centre A1.centre
extrude "Extrude5" cut sketch "Sketch4" against normal blind 14
fillet "Fillet3" radius 3 1 edges at (12.5, -10, -9.6419)
fillet "Fillet3" radius 3 1 edges at (-12.5, -10, -9.6419)
fillet "Fillet4" radius 2.5 1 edges at (0, 15.4771, -14.5)
move_face "OffsetFaces2" offset 1.6 1 faces at (-4.1667, 0, 6.4054)

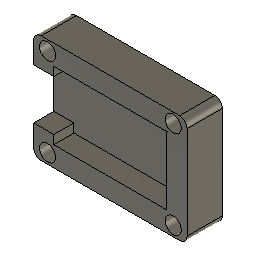
design "Reciever Mount"
part number: 2026-10-04-00-28-57-443
Autodesk Fusion 360 part; units mm, degrees
sketch "Sketch1" plane through (0, 0, 0) normal (0, 1, 0) x (1, 0, 0)
  line L0 (0, 0) -> (30.5, 0)
  line L1 (30.5, 0) -> (30.5, -21.5)
  line L2 (30.5, -21.5) -> (0, -21.5)
  line L3 (0, -21.5) -> (0, 0)
  dimension "d1" = 30.5
  dimension "d2" = 21.5
  constraint horizontal L0
  constraint vertical L1
  constraint horizontal L2
  constraint vertical L3
  constraint coincident L0.start L3.end
  measures "d1" distance of L0.start L0.end
  measures "d2" distance of L0.end L1.end
extrude "Extrude1" add sketch "Sketch1" along normal blind 7
sketch "Sketch2" plane through (0, 0, 0) normal (0, -1, 0) x (1, 0, 0)
  line L0 (30.5, 21.5) -> (0, 21.5)
  line L1 (0, 21.5) -> (0, 0)
  line L2 (0, 0) -> (30.5, 0)
  line L3 (30.5, 0) -> (30.5, 21.5)
  line L4 (4, 4) -> (26.5, 4)
  line L5 (26.5, 4) -> (26.5, 17.5)
  line L6 (26.5, 17.5) -> (4, 17.5)
  line L7 (4, 17.5) -> (4, 4)
  dimension "d5" = -4
extrude "Extrude2" cut sketch "Sketch2" against normal blind 4 contours L4 L5 L6 L7
fillet "Fillet1" radius 1.5 1 edges at (30.5, 3.5, 21.5)
fillet "Fillet1" radius 1.5 1 edges at (30.5, 3.5, 0)
fillet "Fillet1" radius 1.5 2 edges at (0, 3.5, 0) (0, 3.5, 21.5)
sketch "Sketch3" plane through (4, 0, 0) normal (1, 0, 0) x (0, 1, 0)
  line L0 (0, 17.5) -> (0, 4)
  line L1 (0, 4) -> (4, 4)
  line L2 (4, 4) -> (4, 17.5)
  line L3 (4, 17.5) -> (0, 17.5)
  line L4 (4, 5.75) -> (0, 5.75)
  line L5 (0, 5.75) -> (0, 15.75)
  line L6 (0, 15.75) -> (4, 15.75)
  line L7 (4, 15.75) -> (4, 5.75)
  dimension "d14" = 1.75
  dimension "d15" = 10
  constraint horizontal L4
  constraint vertical L5
  constraint horizontal L6
  constraint vertical L7
  constraint coincident L0 L5.end
  constraint coincident L2 L4.start
  measures "d14" distance of L3 L6
  measures "d15" distance of L4.end L5.end
extrude "Extrude3" cut sketch "Sketch3" against normal blind 7 contours L0 L2 L4 L5 L6 L7
sketch "Sketch4" plane through (0, 0, 0) normal (0, -1, 0) x (1, 0, 0)
  line L0 (0, 15.75) -> (4, 15.75)
  line L1 (4, 15.75) -> (4, 17.5)
  line L2 (4, 17.5) -> (26.5, 17.5)
  line L3 (26.5, 17.5) -> (26.5, 4)
  line L4 (26.5, 4) -> (4, 4)
  line L5 (4, 4) -> (4, 5.75)
  line L6 (4, 5.75) -> (0, 5.75)
  line L7 (0, 5.75) -> (0, 1.5)
  arc A0 (0, 1.5) -> (1.5, 0) centre (1.5, 1.5) ccw
  line L8 (1.5, 0) -> (29, 0)
  arc A1 (29, 0) -> (30.5, 1.5) centre (29, 1.5) ccw
  line L9 (30.5, 1.5) -> (30.5, 20)
  arc A2 (30.5, 20) -> (29, 21.5) centre (29, 20) ccw
  line L10 (29, 21.5) -> (1.5, 21.5)
  arc A3 (1.5, 21.5) -> (0, 20) centre (1.5, 20) ccw
  line L11 (0, 20) -> (0, 15.75)
  circle A4 centre (27.75, 2) radius 1.6
  circle A5 centre (2.75, 2) radius 1.6
  line L12 (15.25, 0) -> (15.25, 21.5) construction
  line L13 (15.25, 10.75) -> (0, 10.75)
  circle A6 centre (27.75, 19.5) radius 1.6
  circle A7 centre (2.75, 19.5) radius 1.6
  dimension "d18" = 3.2
  dimension "d19" = 25
  dimension "d20" = 30.5
  dimension "d21" = 2.75
  dimension "d23" = 4
  dimension "d24" = 2
  constraint equal A4 A5
  constraint horizontal A4.centre A5.centre
  constraint midpoint L8 L12.start
  constraint midpoint L10 L12.end
  constraint midpoint L12 L13.start
  constraint perpendicular L12 L13
  constraint symmetric A4 L13 A6
  constraint symmetric A5 L13 A7
  measures "d18" diameter of A4
  measures "d19" horizontal distance of A4.centre A5.centre
  measures "d20" distance of L7 L9
  measures "d21" distance of L9 A4.centre
  measures "d23" distance of L4 L8
  measures "d24" distance of L4 A4.centre
extrude "Extrude4" cut sketch "Sketch4" against normal blind 25 contours A4 | A5 | A6 | A7

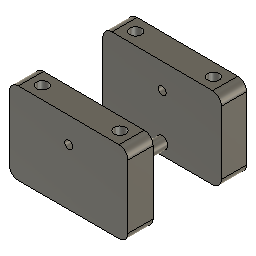
design "Camera Mount"
part number: 2026-10-04-01-04-44-545
Autodesk Fusion 360 part; units mm, degrees
sketch "Sketch1" plane through (0, 0, 0) normal (0, 1, 0) x (1, 0, 0)
  line L0 (0, 0) -> (33.02, 0)
  line L1 (33.02, 0) -> (33.02, -22.66)
  line L2 (0, -22.86) -> (0, 0)
  line L3 (5.6768, -12.4691) -> (25, -12.4691) construction
  line L4 (0, -22.86) -> (33.02, -22.66)
  dimension "d1" = 33.02
  dimension "d3" = 22.86
  dimension "d4" = 22.66
  constraint horizontal L0
  constraint vertical L1
  constraint vertical L2
  constraint coincident L0.start L2.end
  constraint horizontal L3
  measures "d1" distance of L0.start L0.end
  measures "d3" distance of L0.start L2.start
  measures "d4" distance of L0.end L1.end
extrude "Extrude1" add sketch "Sketch1" along normal blind 7 makes body 1
sketch "Sketch2" plane through (0, 0, 0) normal (0, -1, 0) x (1, 0, 0)
  line L0 (0, 0) -> (33.02, 0)
  line L1 (33.02, 0) -> (33.02, 22.66)
  line L2 (14.51, 29.672) -> (14.51, 0) construction
  line L3 (18.51, 30.5215) -> (18.51, 0) construction
  circle A0 centre (16.51, 15.67) radius 1.1
  circle A1 centre (16.51, 3.235) radius 1.6
  line L4 (33.02, 22.66) -> (0, 22.86)
  point P0 (16.51, 26.67)
  dimension "d9" = 2.2
  dimension "d10" = 4
  dimension "d11" = 2
  dimension "d28" = 26.67
  dimension "d40" = 3.2
  dimension "d46" = 11
  constraint coincident L0 L2.end
  constraint perpendicular L0 L2
  constraint coincident L0 L3.end
  constraint perpendicular L0 L3
  measures "d9" diameter of A0
  measures "d10" distance of L2 L3
  measures "d11" distance of L2 A0.centre
  measures "d28" distance of L0 P0
  measures "d40" diameter of A1
  measures "d46" distance of A0.centre P0
extrude "Extrude2" cut sketch "Sketch2" against normal blind 8 contours A0 bodies 1
fillet "Fillet4" radius 2.5 1 edges at (0, 3.5, 0) on bodies 1
sketch "Sketch3" plane through (0, 0, 0) normal (0, 0, -1) x (1, 0, 0)
  line L0 (2.5, 0) -> (2.5, -7)
  line L1 (2.5, -7) -> (33.02, -7)
  line L2 (33.02, 0) -> (2.5, 0)
  circle A0 centre (5.7, -3.4985) radius 1.6
  circle A1 centre (27.32, -3.4985) radius 1.6
  line L3 (33.02, -7) -> (33.02, 0)
  dimension "d48" = 3.2
  dimension "d49" = 3.2
  dimension "d50" = 3.2
  dimension "d51" = 3.5015
  dimension "d52" = 21.62
  constraint horizontal A0.centre A1.centre
  measures "d48" diameter of A0
  measures "d49" diameter of A1
  measures "d50" distance of L0 A0.centre
  measures "d51" distance of L1 A0.centre
  measures "d52" distance of A0.centre A1.centre
ref_plane "WorkPlane2" through (16.51, 16.525, 11.43) normal (0, 1, 0) x (0, 0, 1)
mirror "Mirror1" about plane through (16.51, 16.525, 11.43) normal (0, 1, 0) of bodies 1 makes body 2
extrude "Extrude5" add sketch "Sketch2" against normal blind 26.05 contours A1 bodies 1 2
extrude "Extrude7" cut sketch "Sketch3" against normal blind 80 contours A0 | A1 bodies 1
ref_plane "WorkPlane3" through (16.51, 16.525, 11.43) normal (0, 1, 0) x (0, 0, 1)
sketch "Sketch4" plane through (0, 0, 0) normal (0, 0, -1) x (1, 0, 0)
  line L0 (2.5, -26.05) -> (2.5, -33.05)
  line L1 (2.5, -33.05) -> (33.02, -33.05)
  line L2 (33.02, -26.05) -> (2.5, -26.05)
  circle A0 centre (27.32, -29.4985) radius 1.6
  line L3 (30.52, -26) -> (2.5, -26)
  line L4 (30.52, -33) -> (30.52, -26)
  line L5 (2.5, -33) -> (30.52, -33)
  line L6 (2.5, -26) -> (2.5, -33)
  circle A1 centre (5.7, -29.4985) radius 1.6
  line L7 (33.02, -33.05) -> (33.02, -26.05)
  point P0 (0, -26)
  dimension "d59" = 3.2
  dimension "d60" = 3.2
  dimension "d61" = 3.2
  dimension "d62" = 3.5015
  dimension "d63" = 21.62
  constraint horizontal A0.centre A1.centre
  measures "d59" diameter of A1
  measures "d60" diameter of A0
  measures "d61" distance of A1.centre L6
  measures "d62" distance of A1.centre L5
  measures "d63" distance of A0.centre A1.centre
extrude "Extrude8" cut sketch "Sketch4" against normal blind 43 contours A0 | A1 bodies 1
fillet "Fillet5" radius 2.5 6 edges at (0, 3.5, 22.86) (0, 29.55, 22.86) (33.02, 3.5, 22.66) (33.02, 29.55, 22.66) (33.02, 3.5, 0) (33.02, 29.55, 0) on bodies 1
